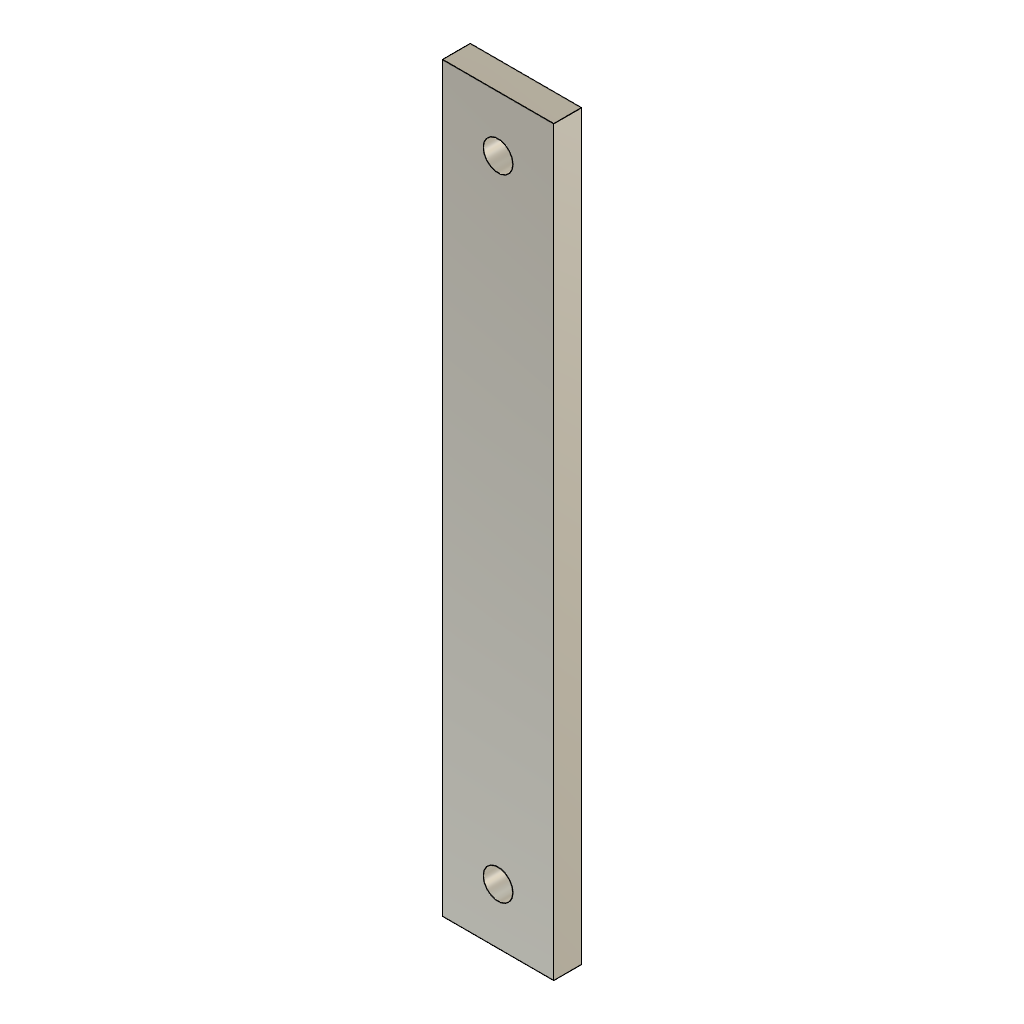
Control Arm Baseline (Autodesk Fusion 360 design; units mm, degrees)
part number: 2026-11-13-14-16-56-971
Autodesk Fusion 360 part; units mm, degrees
sketch "Sketch1" plane through (0, 0, 0) normal (0, 1, 0) x (1, 0, 0)
  line L0 (0, 0) -> (60, 0)
  line L1 (60, 0) -> (60, 400)
  line L2 (60, 400) -> (0, 400)
  line L3 (0, 400) -> (0, 0)
  circle A0 centre (30, 370) radius 8
  circle A1 centre (30, 30) radius 8
  dimension "d1" = 60
  dimension "d2" = 400
  dimension "d3" = 16
  dimension "d4" = 16
  dimension "d5" = 30
  dimension "d6" = 30
  constraint horizontal L0
  constraint vertical L1
  constraint horizontal L2
  constraint vertical L3
  constraint coincident L0.start L3.end
  measures "d1" distance of L0.start L0.end
  measures "d2" distance of L0.start L2.end
  measures "d3" diameter of A0
  measures "d4" diameter of A1
  measures "d5" distance of L0 A1.centre
  measures "d6" distance of L2 A0.centre
extrude "Extrude1" add sketch "Sketch1" along normal blind 15
